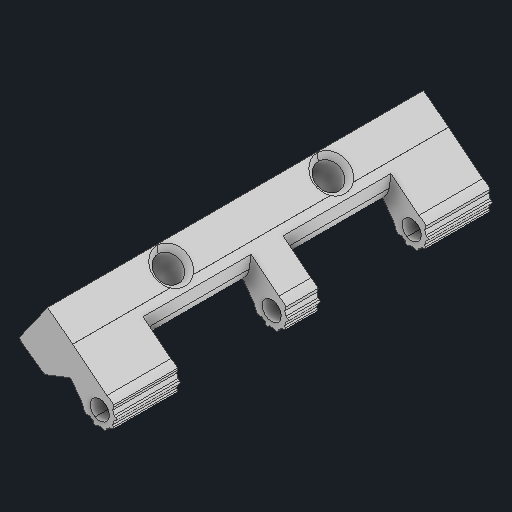
# Autodesk Inventor part: 连杆
Saved by Autodesk Inventor 2025 (Build 290162000, 162)
## iProperties
Created: 2025-08-28
Part Number: 连杆
Material: 常规
Document SubType Name: Modeling
Designer: HZD
Density: 1 g/cm^3
Appearance: 默认
Author: HZD
Autodesk Inventor part; units mm, degrees
ref_plane "YZ Plane" through (0, 0, 0) normal (1, 0, 0) x (0, 1, 0)
sketch "草图1" plane through (0, 0, 0) normal (0, 0, 1) x (1, 0, 0)
  circle A0 centre (0, 0) radius 0.6
  circle A1 centre (0, 0) radius 1.1
  dimension "d0" = 1.2
  dimension "d1" = 0.5
  constraints: 2 centre point, 2 coincident
  measures "d0" diameter of A0
  measures "d1" radial gap between concentric circles of A0 A1
extrude "拉伸1" add sketch "草图1" along normal blind 4
sketch "草图2" plane through (0, 0, 0) normal (0, 0, -1) x (-1, 0, 0)
  circle A0 centre (0, 0) radius 1.1 projected
  line L0 (-0.4447, 1.0061) -> (1.6929, 2.7131)
  line L1 (1.6929, 2.7131) -> (2.4826, 1.7242)
  line L2 (2.4826, 1.7242) -> (1.0812, -0.2025)
  line L3 (3.4475, 0.1877) -> (1.8322, 0.83)
  line L4 (5.082, 1.3401) -> (3.4475, 0.1877)
  line L5 (3.4475, 0.1877) -> (1.8557, 0.8207)
  line L6 (1.8557, 0.8207) -> (3.6581, 2.0914)
  line L7 (3.6581, 2.0914) -> (5.082, 1.3401)
  line L8 (3.6581, 2.0914) -> (1.6929, 2.7131)
  circle A1 centre (0.008, 0.0032) radius 0.5989
  line L9 (1.6929, 2.7131) -> (3.2678, 3.9134)
  line L10 (5.082, 1.3401) -> (3.1889, 4.0253)
  point P0 (2.6516, 0.5042)
  point P1 (-0.4, 1.0247)
  dimension "d46" = 2
  constraints: 22 end point, 3 point on line, 2 point on circle, 1 centre point, 1 midpoint, 1 parallel, 1 perpendicular
  measures "d46" distance of L4.start L3.start
extrude "拉伸2" add sketch "草图2" against normal blind 23.5
ref_plane "工作平面1" through (0, 0, 11.75) normal (0, 0, -1) x (-1, 0, 0)
mirror "镜像1" about plane through (0, 0, 11.75) normal (0, 0, -1) of "拉伸1"
ref_plane "工作平面2" through (-1.7627, 0.5355, 23.5) normal (0.1297676, 0.9915444, 0) x (0.9915444, -0.1297676, 0)
sketch "草图4" plane through (-1.7627, 0.5355, 23.5) normal (0.1297676, 0.9915444, 0) x (0.9915444, -0.1297676, 0)
  line L0 (2.9173, 4) -> (2.9173, 0)
  line L1 (2.9173, 4) -> (0.2173, 4)
  line L2 (0.2173, 4) -> (0.2173, 10.75)
  line L3 (0.2173, 10.75) -> (2.9173, 10.75)
  line L4 (2.9173, 10.75) -> (2.9173, 4)
  line L5 (1.073, 10.75) -> (0.4864, 10.75) projected
  line L6 (2.9173, 10.75) -> (2.9173, 12.75)
  line L7 (2.9173, 11.75) -> (-2.5339, 11.75)
  line L8 (2.9173, 19.5) -> (0.2173, 19.5)
  line L9 (0.2173, 19.5) -> (0.2173, 12.75)
  line L10 (0.2173, 12.75) -> (2.9173, 12.75)
  line L11 (2.9173, 12.75) -> (2.9173, 19.5)
  line L12 (1.073, 12.75) -> (0.4864, 12.75)
  line L13 (0, 4) -> (0.9894, 4) projected
  point P0 (1.8173, 23.5)
  point P1 (0.8138, 4)
  point P2 (0, 10.75)
  dimension "d12" = 2.7
  constraints: 24 end point, 8 symmetric about line, 2 collinear, 2 horizontal, 2 parallel, 1 midpoint, 1 perpendicular, 1 point on line
  measures "d12" distance between parallel lines of L11 L9
extrude "拉伸4" cut sketch "草图4" along normal mid plane 13.25
fillet "圆角5" radius 0.1 1 edges at (-3.4475, 0.1877, 11.75)
fillet "圆角6" radius 0.2 3 edges at (-1.6929, 2.7131, 11.75) (-1.8322, 0.83, 11.75) (-5.082, 1.3401, 11.75)
sketch "草图11" plane through (-3.4917, 0.2189, 0) normal (-0.5762216, -0.8172935, 0) x (0.8172935, -0.5762216, 0)
  circle A0 centre (-0.8027, 6.6796) radius 0.8 projected
  circle A1 centre (-0.8027, 16.6893) radius 0.8 projected
  point P0 (2.9799, 0)
extrude "拉伸9" cut sketch "草图11" against normal blind 23.5
fillet "圆角7" radius 1 2 edges at (-1.5549, 0.4488, 16.125) (-1.5549, 0.4488, 7.375)
sketch "草图12" plane through (0, 0, 0) normal (0, 0, -1) x (-1, 0, 0)
  circle A0 centre (0, 0) radius 1.1
  circle A1 centre (0, 0) radius 0.9
  arc A2 (-0.4447, 1.0061) -> (1.0812, -0.2025) centre (0, 0) ccw projected
  line L0 (-0.8868, -0.1533) -> (-1.1, 0)
  line L1 (-0.888, 0.1467) -> (-1.1, 0)
  line L2 (-0.8046, -0.4032) -> (-0.8899, -0.6466)
  line L3 (-0.6274, -0.6453) -> (-0.8899, -0.6466)
  line L4 (-0.4139, -0.7992) -> (-0.3399, -1.0462)
  line L5 (-0.1283, -0.8908) -> (-0.3399, -1.0462)
  line L6 (0.1349, -0.8898) -> (0.3399, -1.0462)
  line L7 (0.4198, -0.7961) -> (0.3399, -1.0462)
  line L8 (0.6321, -0.6406) -> (0.8899, -0.6466)
  line L9 (0.8076, -0.3973) -> (0.8899, -0.6466)
  line L10 (0.888, -0.1467) -> (1.1, 0)
  line L11 (0.8868, 0.1533) -> (1.1, 0)
  line L12 (0.8046, 0.4032) -> (0.8899, 0.6466)
  line L13 (0.6274, 0.6453) -> (0.8899, 0.6466)
  line L14 (0.4139, 0.7992) -> (0.3399, 1.0462)
  line L15 (0.1283, 0.8908) -> (0.3399, 1.0462)
  line L16 (-0.1349, 0.8898) -> (-0.3399, 1.0462)
  line L17 (-0.4198, 0.7961) -> (-0.3399, 1.0462)
  line L18 (-0.6321, 0.6406) -> (-0.8899, 0.6466)
  line L19 (-0.8076, 0.3973) -> (-0.8899, 0.6466)
  dimension "d51" = 0.2
  dimension "d52" = 0.3
  dimension "d55" = 360
  constraints: 40 end point, 3 point on circle, 2 centre point, 2 coincident, 1 concentric, 51 other
  measures "d51" radial gap between concentric circles of A0 A1
  measures "d52" distance of L1.start L0.start
extrude "拉伸10" cut sketch "草图12" against normal up to surface (23.5 mm away) contours A0 L7 A1 L8 | A0 L5 A1 L6 | A0 L3 A1 L4 | L19 A1 L1 A0 | A0 L0 A1 L2
fillet "圆角8" radius 0.1 16 edges at (0.8899, -0.6466, 11.75) (1.1, 0, 11.75) (0.3399, -1.0462, 11.75) (-0.3399, -1.0462, 11.75) (1.1, 0, 2) (0.8899, -0.6466, 2) (0.3399, -1.0462, 2) (-0.3399, -1.0462, 2) (-0.8899, -0.6466, 2) (-0.8899, -0.6466, 21.5) (-0.3399, -1.0462, 21.5) (0.3399, -1.0462, 21.5) (0.8899, -0.6466, 21.5) (1.1, 0, 21.5) (0.8899, 0.6466, 21.5) (-0.8899, -0.6466, 11.75)
chamfer "倒角1" distance 0.3 angle 45 2 edges at (-2.9947, 3.7053, 6.6796) (-2.9947, 3.7053, 16.6893)
